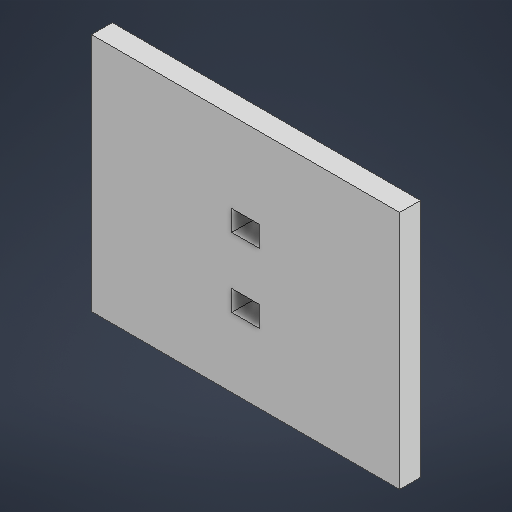
# Autodesk Inventor part: Laser Rx Wall
Saved by Autodesk Inventor 2027.1 (Build 311270010, 270A)
## iProperties
Created: 2026-10-18
Part Number: Laser Rx Wall
Material: Generic
Document SubType Name: Modeling
Designer: Ahmed
Density: 1 g/cm^3
Appearance: Default
Author: Ahmed
Autodesk Inventor part; units mm, degrees
ref_plane "YZ Plane" through (0, 0, 0) normal (1, 0, 0) x (0, 1, 0)
ref_plane "XZ Plane" through (0, 0, 0) normal (0, 1, 0) x (-1, 0, 0)
ref_plane "XY Plane" through (0, 0, 0) normal (0, 0, 1) x (1, 0, 0)
sketch "Sketch1" plane through (0, 0, 0) normal (0, 0, 1) x (1, 0, 0)
  line L0 (0, 0) -> (44.4533, 0)
  line L1 (44.4533, 0) -> (44.4533, 34.607)
  line L2 (44.4533, 34.607) -> (0, 34.607)
  line L3 (0, 34.607) -> (0, 0)
  line L4 (20.2267, 23) -> (24.2267, 23)
  line L5 (24.2267, 23) -> (24.2267, 20)
  line L6 (24.2267, 20) -> (20.2267, 20)
  line L7 (20.2267, 20) -> (20.2267, 23)
  line L8 (22.2267, 34.607) -> (22.2267, 0)
  line L9 (20.2267, 13) -> (24.2267, 13)
  line L10 (24.2267, 13) -> (24.2267, 10)
  line L11 (24.2267, 10) -> (20.2267, 10)
  line L12 (20.2267, 10) -> (20.2267, 13)
  point P0 (22.2267, 10)
  point P1 (22.2267, 20)
  dimension "d0" = 44.4533
  dimension "d1" = 34.607
  dimension "d2" = 4
  dimension "d3" = 3
  dimension "d4" = 4
  dimension "d5" = 3
  dimension "d6" = 10
  dimension "d7" = 20
  constraints: 26 end point, 6 parallel, 4 midpoint, 3 horizontal, 3 perpendicular, 2 point on line
  measures "d0" distance of L1.end L2.end
  measures "d1" distance of L0.end L1.end
  measures "d2" distance of L5.end L6.end
  measures "d3" distance of L4.end L5.end
  measures "d4" distance of L10.end L11.end
  measures "d5" distance of L9.end L10.end
  measures "d6" distance between parallel lines of L0 L11
  measures "d7" distance between parallel lines of L0 L6
extrude "Extrusion1" add sketch "Sketch1" along normal blind 3 contours L3 L2 L8 L4 L7 L6 L9 L12 L11 L0 | L8 L11 L10 L9 L6 L5 L4 L2 L1 L0
body "Solid1"
